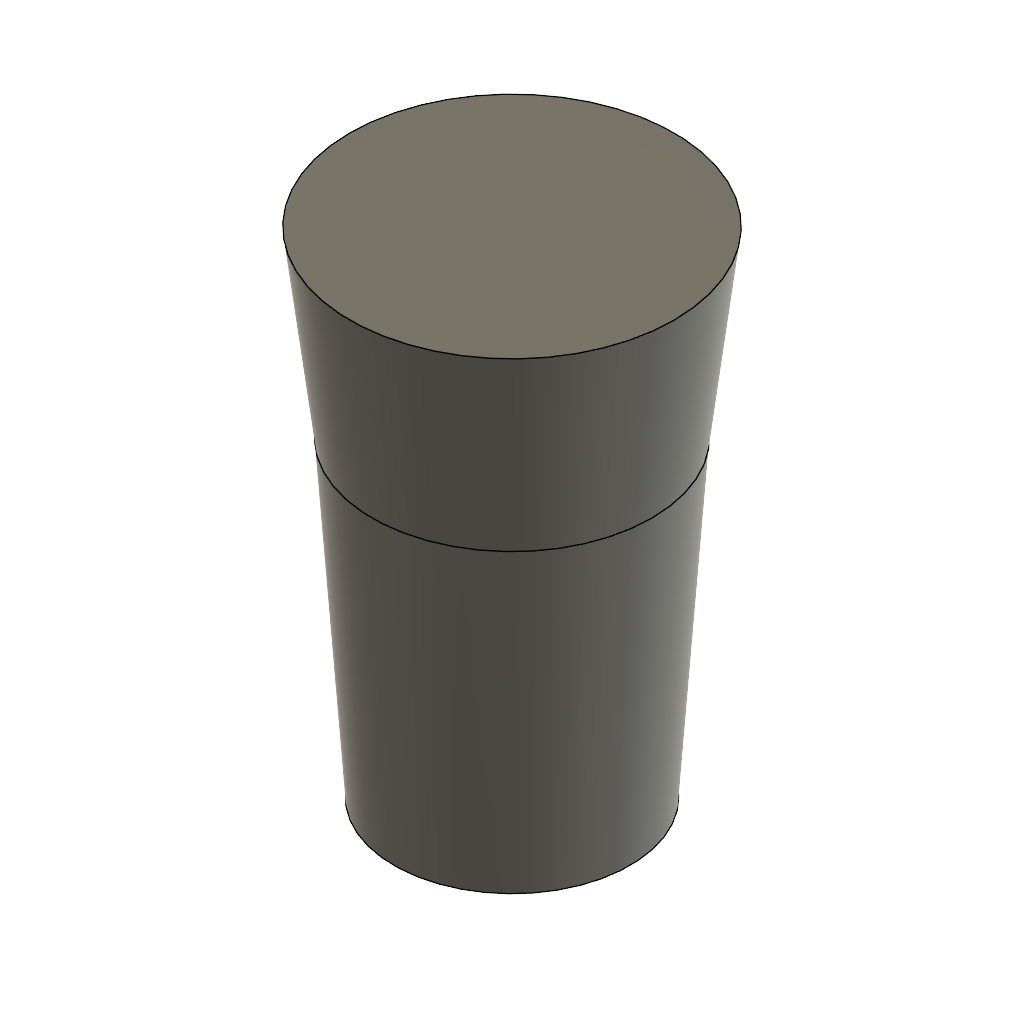
world_sketch (Autodesk Fusion 360 design; units mm, degrees)
part number: 2026-11-27-16-39-49-824
Autodesk Fusion 360 part; units mm, degrees
sketch "CircularProfile" plane through (0, 0, 0) normal (0, 1, 0) x (1, 0, 0)
  circle A0 centre (7, -11) radius 13
extrude "TwoSidedDraft" add sketch "CircularProfile" along normal blind 17 draft 7 and the other way blind 29 draft -4
